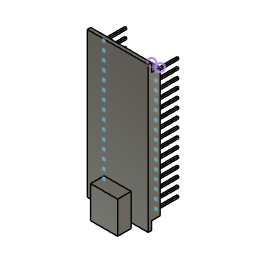
nano v1 (Autodesk Fusion 360 design; units mm, degrees)
Autodesk Fusion 360 part; units mm, degrees
sketch "草图1" plane through (0, 0, 0) normal (0, 1, 0) x (1, 0, 0)
  line L0 (0, 0) -> (18, 0)
  line L1 (18, 0) -> (18, -43)
  line L2 (18, -43) -> (0, -43)
  line L3 (0, -43) -> (0, 0)
  dimension "d1" = 18
  dimension "d2" = 43
  constraint coincident L0.start L3.end
  constraint horizontal L0
  constraint perpendicular L0 L1
  constraint perpendicular L1 L2
  constraint perpendicular L0 L3
  measures "d1" distance of L0.start L0.end
  measures "d2" distance of L0.end L1.end
extrude "拉伸1" add sketch "草图1" along normal blind 1
sketch "草图2" plane through (0, 0, 0) normal (0, -1, 0) x (1, 0, 0)
  line L0 (18, 43) -> (0, 43)
  line L1 (0, 43) -> (0, 0)
  line L2 (0, 0) -> (18, 0)
  line L3 (18, 0) -> (18, 43)
  line L4 (4.9545, 0) -> (12.9545, 0)
  line L5 (12.9545, 0) -> (12.9545, 8)
  line L6 (4.9545, 8) -> (4.9545, 0)
  line L7 (4.9545, 0) -> (4.9545, -1.5)
  line L8 (4.9545, -1.5) -> (12.9545, -1.5)
  line L9 (12.9545, -1.5) -> (12.9545, 0)
  line L10 (12.9545, 8) -> (4.9545, 8)
  dimension "d6" = 8
  dimension "d9" = 1.5
  dimension "d10" = 8
  constraint coincident L2 L4.start
  constraint parallel L2 L4
  constraint perpendicular L4 L5
  constraint perpendicular L4 L7
  constraint perpendicular L7 L8
  measures "d6" distance of L4.start L4.end
  measures "d9" distance of L4.start L7.end
  measures "d10" distance of L7.end L8.end
extrude "拉伸2" add sketch "草图2" along normal blind 4 contours L2 L4 L7 L8 L9 | L2 L4 L5 L6 L10
sketch "草图3" plane through (0, 1, 0) normal (0, 1, 0) x (-1, 0, 0)
  line L0 (0, 43) -> (-18, 43)
  line L1 (-18, 43) -> (-18, 0)
  line L2 (-18, 0) -> (0, 0)
  line L3 (0, 0) -> (0, 43)
  line L4 (-18, 21.5) -> (-18, 40)
  line L5 (-18, 40) -> (-15.46, 40)
  line L6 (-15.46, 40) -> (-15.46, 3)
  line L7 (-15.46, 3) -> (-18, 3)
  line L8 (-18, 3) -> (-18, 21.5)
  line L9 (-9, 43) -> (-9, 0)
  line L10 (0, 21.5) -> (0, 40)
  line L11 (0, 3) -> (0, 21.5)
  line L12 (-2.54, 40) -> (-2.54, 3)
  line L13 (0, 40) -> (-2.54, 40)
  line L14 (-2.54, 3) -> (0, 3)
  dimension "d14" = 18.5
  dimension "d15" = 2.54
  dimension "d16" = 37
  constraint midpoint L1 L4.start
  constraint parallel L1 L4
  constraint perpendicular L4 L5
  constraint perpendicular L5 L6
  constraint coincident L1 L7.end
  constraint perpendicular L1 L7
  constraint midpoint L0 L9.start
  constraint midpoint L2 L9.end
  constraint symmetric L4.start L9 L10.start
  constraint symmetric L4.end L9 L10.end
  constraint symmetric L5.end L9 L12.start
  constraint symmetric L6.end L9 L12.end
  constraint symmetric L7.end L9 L11.start
  measures "d14" distance of L4.start L4.end
  measures "d15" distance of L4.end L5.end
  measures "d16" distance of L5.end L6.end
extrude "拉伸3" add sketch "草图3" along normal blind 2.54 contours L1 L4 L5 L6 L7 L8
extrude "拉伸4" add sketch "草图3" along normal blind 2.54 contours L3 L10 L11 L12 L13 L14
sketch "草图4" plane through (0, 3.54, 0) normal (0, 1, 0) x (-1, 0, 0)
  line L0 (-18, 3) -> (-15.46, 3)
  line L1 (-15.46, 3) -> (-15.46, 40)
  line L2 (-15.46, 40) -> (-18, 40)
  line L3 (-18, 40) -> (-18, 3)
extrude "拉伸5" add 1 faces at (17.1533, 2.6933, 3) along direction (0, 0, -1) blind 0.5
extrude "拉伸6" add 1 faces at (16.3067, 2.6933, 40) along direction (0, 0, 1) blind 0.5
extrude "拉伸7" add 1 faces at (0.8467, 1.8467, 40) along direction (0, 0, 1) blind 0.5
extrude "拉伸8" add 1 faces at (1.6933, 1.8467, 3) along direction (0, 0, -1) blind 0.5
sketch "草图6" plane through (0, 3.54, 0) normal (0, 1, 0) x (-1, 0, 0)
  line L0 (-18, 40.5) -> (-15.46, 40.5)
  line L1 (-16.73, 39.27) -> (-16.48, 39.27)
  line L2 (-16.48, 39.27) -> (-16.48, 38.77)
  line L3 (-16.48, 38.77) -> (-16.98, 38.77)
  line L4 (-16.98, 38.77) -> (-16.98, 39.27)
  line L5 (-16.98, 39.27) -> (-16.73, 39.27)
  line L6 (-1.08, 39.27) -> (-1.08, 38.77)
  line L7 (-1.33, 39.27) -> (-1.08, 39.27)
  line L8 (-1.58, 39.27) -> (-1.33, 39.27)
  line L9 (-1.58, 38.77) -> (-1.58, 39.27)
  line L10 (-1.08, 38.77) -> (-1.58, 38.77)
  line L11 (-16.48, 36.7414) -> (-16.48, 36.2414)
  line L12 (-16.73, 36.7414) -> (-16.48, 36.7414)
  line L13 (-16.98, 36.7414) -> (-16.73, 36.7414)
  line L14 (-16.98, 36.2414) -> (-16.98, 36.7414)
  line L15 (-16.48, 36.2414) -> (-16.98, 36.2414)
  line L16 (-1.08, 36.7414) -> (-1.08, 36.2414)
  line L17 (-1.33, 36.7414) -> (-1.08, 36.7414)
  line L18 (-1.58, 36.7414) -> (-1.33, 36.7414)
  line L19 (-1.58, 36.2414) -> (-1.58, 36.7414)
  line L20 (-1.08, 36.2414) -> (-1.58, 36.2414)
  line L21 (-16.48, 34.2129) -> (-16.48, 33.7129)
  line L22 (-16.73, 34.2129) -> (-16.48, 34.2129)
  line L23 (-16.98, 34.2129) -> (-16.73, 34.2129)
  line L24 (-16.98, 33.7129) -> (-16.98, 34.2129)
  line L25 (-16.48, 33.7129) -> (-16.98, 33.7129)
  line L26 (-1.08, 34.2129) -> (-1.08, 33.7129)
  line L27 (-1.33, 34.2129) -> (-1.08, 34.2129)
  line L28 (-1.58, 34.2129) -> (-1.33, 34.2129)
  line L29 (-1.58, 33.7129) -> (-1.58, 34.2129)
  line L30 (-1.08, 33.7129) -> (-1.58, 33.7129)
  line L31 (-16.48, 31.6843) -> (-16.48, 31.1843)
  line L32 (-16.73, 31.6843) -> (-16.48, 31.6843)
  line L33 (-16.98, 31.6843) -> (-16.73, 31.6843)
  line L34 (-16.98, 31.1843) -> (-16.98, 31.6843)
  line L35 (-16.48, 31.1843) -> (-16.98, 31.1843)
  line L36 (-1.08, 31.6843) -> (-1.08, 31.1843)
  line L37 (-1.33, 31.6843) -> (-1.08, 31.6843)
  line L38 (-1.58, 31.6843) -> (-1.33, 31.6843)
  line L39 (-1.58, 31.1843) -> (-1.58, 31.6843)
  line L40 (-1.08, 31.1843) -> (-1.58, 31.1843)
  line L41 (-16.48, 29.1557) -> (-16.48, 28.6557)
  line L42 (-16.73, 29.1557) -> (-16.48, 29.1557)
  line L43 (-16.98, 29.1557) -> (-16.73, 29.1557)
  line L44 (-16.98, 28.6557) -> (-16.98, 29.1557)
  line L45 (-16.48, 28.6557) -> (-16.98, 28.6557)
  line L46 (-1.08, 29.1557) -> (-1.08, 28.6557)
  line L47 (-1.33, 29.1557) -> (-1.08, 29.1557)
  line L48 (-1.58, 29.1557) -> (-1.33, 29.1557)
  line L49 (-1.58, 28.6557) -> (-1.58, 29.1557)
  line L50 (-1.08, 28.6557) -> (-1.58, 28.6557)
  line L51 (-16.48, 26.6271) -> (-16.48, 26.1271)
  line L52 (-16.73, 26.6271) -> (-16.48, 26.6271)
  line L53 (-16.98, 26.6271) -> (-16.73, 26.6271)
  line L54 (-16.98, 26.1271) -> (-16.98, 26.6271)
  line L55 (-16.48, 26.1271) -> (-16.98, 26.1271)
  line L56 (-1.08, 26.6271) -> (-1.08, 26.1271)
  line L57 (-1.33, 26.6271) -> (-1.08, 26.6271)
  line L58 (-1.58, 26.6271) -> (-1.33, 26.6271)
  line L59 (-1.58, 26.1271) -> (-1.58, 26.6271)
  line L60 (-1.08, 26.1271) -> (-1.58, 26.1271)
  line L61 (-16.48, 24.0986) -> (-16.48, 23.5986)
  line L62 (-16.73, 24.0986) -> (-16.48, 24.0986)
  line L63 (-16.98, 24.0986) -> (-16.73, 24.0986)
  line L64 (-16.98, 23.5986) -> (-16.98, 24.0986)
  line L65 (-16.48, 23.5986) -> (-16.98, 23.5986)
  line L66 (-1.08, 24.0986) -> (-1.08, 23.5986)
  line L67 (-1.33, 24.0986) -> (-1.08, 24.0986)
  line L68 (-1.58, 24.0986) -> (-1.33, 24.0986)
  line L69 (-1.58, 23.5986) -> (-1.58, 24.0986)
  line L70 (-1.08, 23.5986) -> (-1.58, 23.5986)
  line L71 (-16.48, 21.57) -> (-16.48, 21.07)
  line L72 (-16.73, 21.57) -> (-16.48, 21.57)
  line L73 (-16.98, 21.57) -> (-16.73, 21.57)
  line L74 (-16.98, 21.07) -> (-16.98, 21.57)
  line L75 (-16.48, 21.07) -> (-16.98, 21.07)
  line L76 (-1.08, 21.57) -> (-1.08, 21.07)
  line L77 (-1.33, 21.57) -> (-1.08, 21.57)
  line L78 (-1.58, 21.57) -> (-1.33, 21.57)
  line L79 (-1.58, 21.07) -> (-1.58, 21.57)
  line L80 (-1.08, 21.07) -> (-1.58, 21.07)
  line L81 (-16.48, 19.0414) -> (-16.48, 18.5414)
  line L82 (-16.73, 19.0414) -> (-16.48, 19.0414)
  line L83 (-16.98, 19.0414) -> (-16.73, 19.0414)
  line L84 (-16.98, 18.5414) -> (-16.98, 19.0414)
  line L85 (-16.48, 18.5414) -> (-16.98, 18.5414)
  line L86 (-1.08, 19.0414) -> (-1.08, 18.5414)
  line L87 (-1.33, 19.0414) -> (-1.08, 19.0414)
  line L88 (-1.58, 19.0414) -> (-1.33, 19.0414)
  line L89 (-1.58, 18.5414) -> (-1.58, 19.0414)
  line L90 (-1.08, 18.5414) -> (-1.58, 18.5414)
  line L91 (-16.48, 16.5129) -> (-16.48, 16.0129)
  line L92 (-16.73, 16.5129) -> (-16.48, 16.5129)
  line L93 (-16.98, 16.5129) -> (-16.73, 16.5129)
  line L94 (-16.98, 16.0129) -> (-16.98, 16.5129)
  line L95 (-16.48, 16.0129) -> (-16.98, 16.0129)
  line L96 (-1.08, 16.5129) -> (-1.08, 16.0129)
  line L97 (-1.33, 16.5129) -> (-1.08, 16.5129)
  line L98 (-1.58, 16.5129) -> (-1.33, 16.5129)
  line L99 (-1.58, 16.0129) -> (-1.58, 16.5129)
  line L100 (-1.08, 16.0129) -> (-1.58, 16.0129)
  line L101 (-16.48, 13.9843) -> (-16.48, 13.4843)
  line L102 (-16.73, 13.9843) -> (-16.48, 13.9843)
  line L103 (-16.98, 13.9843) -> (-16.73, 13.9843)
  line L104 (-16.98, 13.4843) -> (-16.98, 13.9843)
  line L105 (-16.48, 13.4843) -> (-16.98, 13.4843)
  line L106 (-1.08, 13.9843) -> (-1.08, 13.4843)
  line L107 (-1.33, 13.9843) -> (-1.08, 13.9843)
  line L108 (-1.58, 13.9843) -> (-1.33, 13.9843)
  line L109 (-1.58, 13.4843) -> (-1.58, 13.9843)
  line L110 (-1.08, 13.4843) -> (-1.58, 13.4843)
  line L111 (-16.48, 11.4557) -> (-16.48, 10.9557)
  line L112 (-16.73, 11.4557) -> (-16.48, 11.4557)
  line L113 (-16.98, 11.4557) -> (-16.73, 11.4557)
  line L114 (-16.98, 10.9557) -> (-16.98, 11.4557)
  line L115 (-16.48, 10.9557) -> (-16.98, 10.9557)
  line L116 (-1.08, 11.4557) -> (-1.08, 10.9557)
  line L117 (-1.33, 11.4557) -> (-1.08, 11.4557)
  line L118 (-1.58, 11.4557) -> (-1.33, 11.4557)
  line L119 (-1.58, 10.9557) -> (-1.58, 11.4557)
  line L120 (-1.08, 10.9557) -> (-1.58, 10.9557)
  line L121 (-16.48, 8.9271) -> (-16.48, 8.4271)
  line L122 (-16.73, 8.9271) -> (-16.48, 8.9271)
  line L123 (-16.98, 8.9271) -> (-16.73, 8.9271)
  line L124 (-16.98, 8.4271) -> (-16.98, 8.9271)
  line L125 (-16.48, 8.4271) -> (-16.98, 8.4271)
  line L126 (-1.08, 8.9271) -> (-1.08, 8.4271)
  line L127 (-1.33, 8.9271) -> (-1.08, 8.9271)
  line L128 (-1.58, 8.9271) -> (-1.33, 8.9271)
  line L129 (-1.58, 8.4271) -> (-1.58, 8.9271)
  line L130 (-1.08, 8.4271) -> (-1.58, 8.4271)
  line L131 (-16.48, 6.3986) -> (-16.48, 5.8986)
  line L132 (-16.73, 6.3986) -> (-16.48, 6.3986)
  line L133 (-16.98, 6.3986) -> (-16.73, 6.3986)
  line L134 (-16.98, 5.8986) -> (-16.98, 6.3986)
  line L135 (-16.48, 5.8986) -> (-16.98, 5.8986)
  line L136 (-1.08, 6.3986) -> (-1.08, 5.8986)
  line L137 (-1.33, 6.3986) -> (-1.08, 6.3986)
  line L138 (-1.58, 6.3986) -> (-1.33, 6.3986)
  line L139 (-1.58, 5.8986) -> (-1.58, 6.3986)
  line L140 (-1.08, 5.8986) -> (-1.58, 5.8986)
  line L141 (-16.48, 3.87) -> (-16.48, 3.37)
  line L142 (-16.73, 3.87) -> (-16.48, 3.87)
  line L143 (-16.98, 3.87) -> (-16.73, 3.87)
  line L144 (-16.98, 3.37) -> (-16.98, 3.87)
  line L145 (-16.48, 3.37) -> (-16.98, 3.37)
  line L146 (-1.08, 3.87) -> (-1.08, 3.37)
  line L147 (-1.33, 3.87) -> (-1.08, 3.87)
  line L148 (-1.58, 3.87) -> (-1.33, 3.87)
  line L149 (-1.58, 3.37) -> (-1.58, 3.87)
  line L150 (-1.08, 3.37) -> (-1.58, 3.37)
  dimension "d35" = 0.25
  dimension "d36" = 0.5
  dimension "d37" = 0.5
  dimension "d38" = 0.5
  dimension "d43" = 15.4
  dimension "d44" = -35.4
  constraint perpendicular L1 L2
  constraint perpendicular L2 L3
  constraint perpendicular L3 L4
  measures "d35" distance of L1.start L1.end
  measures "d36" distance of L1.end L2.end
  measures "d37" distance of L2.end L3.end
  measures "d38" distance of L3.end L4.end
extrude "拉伸9" add sketch "草图6" along normal blind 6.5 contours L1 L2 L3 L4 L5
extrude "拉伸10" add sketch "草图6" along normal blind 6.5 contours L11 L12 L13 L14 L15 | L21 L22 L23 L24 L25 | L31 L32 L33 L34 L35 | L41 L42 L43 L44 L45 | L51 L52 L53 L54 L55 | L61 L62 L63 L64 L65 | L71 L72 L73 L74 L75 | L81 L82 L83 L84 L85 | L91 L92 L93 L94 L95 | L101 L102 L103 L104 L105 | L111 L112 L113 L114 L115 | L121 L122 L123 L124 L125 | L131 L132 L133 L134 L135 | L141 L142 L143 L144 L145
extrude "拉伸11" add sketch "草图6" along normal blind 6.5 contours L6 L7 L8 L9 L10 | L16 L17 L18 L19 L20 | L26 L27 L28 L29 L30 | L36 L37 L38 L39 L40 | L46 L47 L48 L49 L50 | L56 L57 L58 L59 L60 | L66 L67 L68 L69 L70 | L76 L77 L78 L79 L80 | L86 L87 L88 L89 L90 | L96 L97 L98 L99 L100 | L106 L107 L108 L109 L110 | L116 L117 L118 L119 L120 | L126 L127 L128 L129 L130 | L136 L137 L138 L139 L140 | L146 L147 L148 L149 L150
